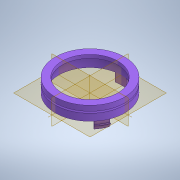
# Autodesk Inventor part: Palm_Support
Saved by Autodesk Inventor 2021 (Build 250183000, 183)
## iProperties
Created: 2026-04-22
Part Number: Palm_Support
Material: Generic
Document SubType Name: Modeling
Designer: Admin
Density: 1 g/cm^3
Appearance: Violet
Author: Admin
Autodesk Inventor part; units mm, degrees
sketch "Sketch2" plane through (0, 0, 0) normal (0, 0, 1) x (1, 0, 0)
  line L0 (-18, 0) -> (-20, 0)
  line L1 (-20, 0) -> (-20, 8)
  line L2 (-20, 8) -> (-16, 8)
  line L3 (-16, 8) -> (-16, 6)
  line L4 (-16, 6) -> (-18, 6)
  line L5 (-18, 6) -> (-18, 0)
  line L6 (0, 9.6) -> (0, -1.6) projected
  line L7 (-24, 0) -> (4, 0) projected
  line L8 (0, -1.6) -> (0, 9.6) projected
  point P0 (0, 0)
  dimension "d1" = 20
  dimension "d2" = 16
  dimension "d3" = 2
  dimension "d4" = 2
  dimension "d5" = 8
  constraints: 12 end point, 5 perpendicular, 1 horizontal, 1 point on line
  measures "d1" distance between parallel lines of L6 L1
  measures "d2" distance between parallel lines of L6 L3
  measures "d3" distance between parallel lines of L3 L5
  measures "d4" distance between parallel lines of L4 L2
  measures "d5" distance between parallel lines of L2 L0
revolve "Revolution1" add sketch "Sketch2" angle 360 about axis through (0, -10, 0) along (0, 1, 0)
sketch "Sketch5" plane through (0, 0, 0) normal (1, 0, 0) x (0, 1, 0)
  line L0 (0, -20) -> (8, -20) projected
  line L1 (0, -18) -> (0, 18) projected
  line L2 (0, -18) -> (-5, -18)
  line L3 (-5, -18) -> (-5, -18.4989)
  line L4 (-5, -18.4989) -> (-2.4, -20)
  line L5 (-2.4, -20) -> (-2.4, -19)
  line L6 (-2.4, -19) -> (2.2331, -19)
  line L7 (0, 26) -> (0, -30) projected
  line L8 (-11.2, 0) -> (11.2, 0) projected
  point P0 (0, 0)
  point P1 (0, -19)
  point P2 (-3.5547, -18)
  dimension "d23" = 1
  dimension "d27" = 2.4
  dimension "d28" = 5
  dimension "d33" = 30
  constraints: 10 end point, 2 horizontal, 1 parallel, 1 perpendicular, 1 point on line, 1 other
  measures "d23" distance between parallel lines of L6 L0
  measures "d27" distance of the line from the sketch origin of L5
  measures "d28" distance of the line from the sketch origin of L3
  measures "d33" angle of L2 L4
revolve "Revolution2" add sketch "Sketch5" angle 20 mid plane about axis through (0, -10, 0) along (0, 1, 0)
pattern_circular "Circular Pattern2" count 3 over 360 about axis through (0, -10, 0) along (0, 1, 0) of "Revolution2"
sketch "Sketch6" plane through (0, 0, 0) normal (1, 0, 0) x (0, 1, 0)
  line L0 (0, -20) -> (8, -20) projected
  line L1 (8, -20) -> (8, 20) projected
  line L2 (5, -20) -> (5, -19)
  line L3 (5, -19) -> (4, -20)
  line L4 (-7.6, 0) -> (10.6, 0) projected
  point P0 (0, 0)
  dimension "d34" = 1
  dimension "d35" = 3
  constraints: 4 end point, 2 midpoint, 1 point on line, 1 vertical
  measures "d34" distance of L2.start L2.end
  measures "d35" distance between parallel lines of L1 L2
revolve "Revolution3" cut sketch "Sketch6" angle 360 about axis through (0, -10, 0) along (0, 1, 0)
body "Solid1"
